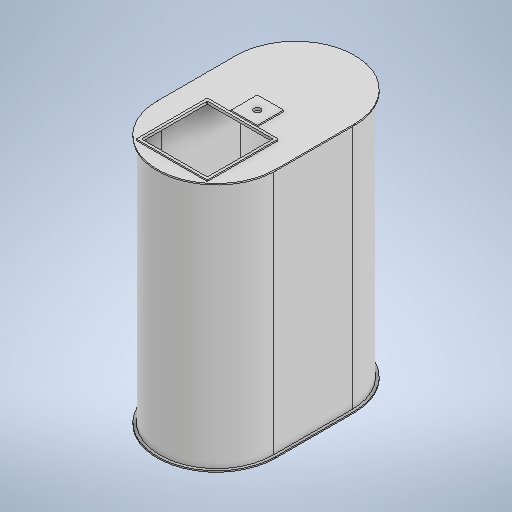
# Autodesk Inventor part: RDS-1001 Tank 2m3 Parfino
Saved by Autodesk Inventor 2026 (Build 300175000, 175)
## iProperties
Created: 2026-10-12
Part Number: RDS-1001 Tank 2m3 Parfino
Material: Generic
Description: Tank 2 m3 Parfino, obround 1500x860 H1900, wall 10
Document SubType Name: Modeling
Designer: admin
Stock Number: Емкость 2 м3 Парфино (ПЭ), овал 1500х860, H1900
Mass: 95905.8 g
Surface Area: 191956 cm^2
Volume: 95905.8 cm^3
Density: 1 g/cm^3
Appearance: Default
Author: admin
Autodesk Inventor part; units mm, degrees
ref_plane "YZ Plane" through (0, 0, 0) normal (1, 0, 0) x (0, 1, 0)
ref_plane "XZ Plane" through (0, 0, 0) normal (0, 1, 0) x (-1, 0, 0)
ref_plane "XY Plane" through (0, 0, 0) normal (0, 0, 1) x (1, 0, 0)
sketch "Sketch1" plane through (0, 0, 0) normal (0, 1, 0) x (-1, 0, 0)
  line L0 (-430, -320) -> (-430, 280)
  line L1 (430, 280) -> (430, -320)
  arc A0 (430, 280) -> (-430, 280) centre (0, 280) ccw
  arc A1 (-430, -320) -> (430, -320) centre (0, -320) ccw
  dimension "d0" = 430
  dimension "d1" = 600
  constraints: 4 end point, 4 point on circle, 4 tangent, 2 centre point, 1 equal radius
  measures "d0" radius of A0
  measures "d1" distance of L0.start L0.end
extrude "Extrusion1" add sketch "Sketch1" along normal blind 1900
shell "Shell1" thickness 10 removed faces 0
sketch "Sketch3" plane through (0, 1900, 0) normal (0, 1, 0) x (1, 0, 0)
  circle A0 centre (0, 370) radius 50
  circle A1 centre (0, -300) radius 250
  line L0 (-430, 320) -> (-430, -280) projected
  point P0 (-430, 20)
  point P1 (-430, 20)
  dimension "d10" = 100
  dimension "d11" = 500
  dimension "d14" = 320
  dimension "d15" = 430
  dimension "d16" = 350
  dimension "d17" = 430
  constraints: 2 centre point, 2 midpoint
  measures "d10" diameter of A0
  measures "d11" diameter of A1
  measures "d14" vertical distance of point (-430, 20) A1.centre
  measures "d15" distance from line of A1.centre L0
  measures "d16" vertical distance of point (-430, 20) A0.centre
  measures "d17" distance from line of A0.centre L0
extrude "Extrusion3" cut sketch "Sketch3" along normal mid plane 40
sketch "Эскиз4" plane through (0, 0, 0) normal (0, -1, 0) x (1, 0, 0)
  arc A0 (430, 280) -> (-430, 280) centre (0, 280) ccw projected
  arc A1 (450, 280) -> (-450, 280) centre (0, 280) ccw
  arc A2 (-430, -320) -> (430, -320) centre (0, -320) ccw projected
  arc A3 (-450, -320) -> (450, -320) centre (0, -320) ccw
  line L0 (-450, 280) -> (-450, -320)
  line L1 (450, -320) -> (450, 280)
  point P0 (0, 0)
  dimension "d18" = 900
  dimension "d19" = 900
  dimension "d20" = 600
  dimension "d21" = 450
  dimension "d22" = 450
  constraints: 4 end point, 4 point on circle, 2 centre point, 2 coincident, 1 parallel
  measures "d18" diameter of A1
  measures "d19" diameter of A3
  measures "d20" distance of L1.start L1.end
  measures "d21" distance from line of point (0, 0) L1
  measures "d22" distance from line of point (0, 0) L0
extrude "Выдавливание4" add sketch "Эскиз4" against normal blind 10
sketch "Эскиз5" plane through (0, 1900, 0) normal (0, 1, 0) x (1, 0, 0)
  arc A0 (450, 320) -> (-450, 320) centre (0, 320) ccw projected
  arc A1 (450, 320) -> (-450, 320) centre (0, 320) ccw
  arc A2 (-450, -280) -> (450, -280) centre (0, -280) ccw projected
  arc A3 (-450, -280) -> (450, -280) centre (0, -280) ccw
  line L0 (450, -280) -> (450, 320) projected
  line L1 (450, 320) -> (450, -280)
  line L2 (-450, -280) -> (-450, 320)
  point P0 (0, 0)
  dimension "d26" = 900
  dimension "d27" = 450
  constraints: 4 end point, 4 point on circle, 2 centre point, 2 coincident, 1 parallel, 1 point on line
  measures "d26" diameter of A3
  measures "d27" distance from line of point (0, 0) L2
extrude "Выдавливание5" add sketch "Эскиз5" against normal blind 10
sketch "Эскиз6" plane through (0, 1900, 0) normal (0, 1, 0) x (1, 0, 0)
  line L0 (245, -600) -> (-245, -600)
  line L1 (-250, -595) -> (-250, -105)
  line L2 (-245, -100) -> (245, -100)
  line L3 (250, -105) -> (250, -595)
  line L4 (250, -600) -> (-250, -100) construction
  line L5 (-250, -600) -> (250, -100) construction
  circle A0 centre (0, 30) radius 25
  line L6 (-450, 320) -> (-450, -280) projected
  arc A1 (-250, -595) -> (-245, -600) centre (-245, -595) ccw
  arc A2 (-245, -100) -> (-250, -105) centre (-245, -105) ccw
  arc A3 (250, -105) -> (245, -100) centre (245, -105) ccw
  arc A4 (245, -600) -> (250, -595) centre (245, -595) ccw
  point P0 (0, 0)
  point P1 (0, -350)
  point P2 (-250, -350)
  dimension "d30" = 500
  dimension "d31" = 500
  dimension "d32" = 350
  dimension "d33" = 250
  dimension "d34" = 50
  dimension "d35" = 30
  dimension "d36" = 450
  dimension "d39" = 5
  constraints: 12 end point, 8 point on circle, 8 point on line, 8 tangent, 5 centre point, 3 equal radius, 3 midpoint, 2 parallel, 1 horizontal, 1 perpendicular
  measures "d30" distance of L4.end L5.end
  measures "d31" distance of L5.start L4.end
  measures "d32" vertical distance of point (0, 0) point (-250, -350)
  measures "d33" distance from line of point (0, 0) L1
  measures "d34" diameter of A0
  measures "d35" distance of point (0, 0) A0.centre
  measures "d36" distance from line of A0.centre L6
  measures "d39" radius of A1
extrude "Выдавливание6" cut sketch "Эскиз6" against normal blind 10
sketch "Эскиз7" plane through (0, 1900, 0) normal (0, 1, 0) x (1, 0, 0)
  line L0 (100, -70) -> (-100, -70)
  line L1 (-100, -70) -> (-100, 130)
  line L2 (-100, 130) -> (100, 130)
  line L3 (100, 130) -> (100, -70)
  circle A0 centre (0, 30) radius 25 projected
  line L4 (100, -70) -> (-100, 130) construction
  line L5 (-100, -70) -> (100, 130) construction
  line L6 (245, -100) -> (-245, -100) projected
  arc A1 (-245, -100) -> (-250, -105) centre (-245, -105) ccw projected
  line L7 (-250, -105) -> (-250, -595) projected
  line L8 (250, -595) -> (250, -105) projected
  line L9 (-245, -600) -> (245, -600) projected
  arc A2 (245, -600) -> (250, -595) centre (245, -595) ccw projected
  arc A3 (250, -105) -> (245, -100) centre (245, -105) ccw projected
  line L10 (245, -600) -> (-245, -600) projected
  line L11 (245, -600) -> (-245, -600) projected
  line L12 (-245, -600) -> (245, -600) projected
  line L13 (-245, -100) -> (245, -100) projected
  line L14 (245, -100) -> (-245, -100) projected
  line L15 (250, -105) -> (250, -595) projected
  line L16 (250, -105) -> (250, -595) projected
  line L17 (250, -595) -> (250, -105) projected
  arc A4 (250, -105) -> (245, -100) centre (245, -105) ccw projected
  arc A5 (250, -105) -> (245, -100) centre (245, -105) ccw projected
  arc A6 (250, -105) -> (245, -100) centre (245, -105) ccw projected
  arc A7 (245, -600) -> (250, -595) centre (245, -595) ccw projected
  arc A8 (245, -600) -> (250, -595) centre (245, -595) ccw projected
  arc A9 (245, -600) -> (250, -595) centre (245, -595) ccw projected
  arc A10 (-245, -100) -> (-250, -105) centre (-245, -105) ccw projected
  line L18 (-250, -595) -> (-250, -105) projected
  arc A11 (-250, -595) -> (-245, -600) centre (-245, -595) ccw projected
  arc A12 (-245, -100) -> (-250, -105) centre (-245, -105) ccw projected
  arc A13 (-245, -100) -> (-250, -105) centre (-245, -105) ccw projected
  line L19 (-245, -100) -> (245, -100) projected
  line L20 (-250, -595) -> (-250, -105) projected
  line L21 (-250, -105) -> (-250, -595) projected
  arc A14 (-250, -595) -> (-245, -600) centre (-245, -595) ccw projected
  arc A15 (-250, -595) -> (-245, -600) centre (-245, -595) ccw projected
  arc A16 (-250, -595) -> (-245, -600) centre (-245, -595) ccw projected
  line L22 (265, -80) -> (-265, -80)
  line L23 (-270, -85) -> (-270, -615)
  line L24 (-265, -620) -> (265, -620)
  line L25 (270, -615) -> (270, -85)
  line L26 (270, -80) -> (-270, -620) construction
  line L27 (-270, -80) -> (270, -620) construction
  arc A17 (-270, -615) -> (-265, -620) centre (-265, -615) ccw
  arc A18 (-265, -80) -> (-270, -85) centre (-265, -85) ccw
  arc A19 (270, -85) -> (265, -80) centre (265, -85) ccw
  arc A20 (265, -620) -> (270, -615) centre (265, -615) ccw
  point P0 (0, 0)
  point P1 (0, -350)
  point P2 (-270, -350)
  dimension "d40" = 200
  dimension "d41" = 200
  dimension "d42" = 540
  dimension "d43" = 540
  dimension "d44" = 5
  dimension "d45" = 350
  dimension "d46" = 270
  constraints: 24 end point, 8 point on circle, 8 point on line, 8 tangent, 5 midpoint, 4 centre point, 4 parallel, 3 equal radius, 2 horizontal, 2 perpendicular, 2 other
  measures "d40" distance of L1.end L2.end
  measures "d41" distance of L0.end L1.end
  measures "d42" distance of L27.end L26.end
  measures "d43" distance of L26.end L27.start
  measures "d44" radius of A17
  measures "d45" vertical distance of point (0, 0) point (-270, -350)
  measures "d46" distance from line of point (0, 0) L23
extrude "Выдавливание7" add sketch "Эскиз7" along normal blind 10
equation "\"d0\" = 0.5 * Tank01_Width"
equation "\"d1\" = Tank01_Length - Tank01_Width"
equation "\"d2\" = Tank01_Height"
equation "\"d4\" = Tank01_Wall_Thickness"
equation "\"d10\" = Tank01_Mixer_Hole_Diam"
equation "\"d12\" = 4 * Tank01_Wall_Thickness"
equation "\"Tank01_Length\" = 1460"
equation "\"Tank01_Width\" = 860"
equation "\"Tank01_Height\" = 1900"
equation "\"Tank01_Wall_Thickness\" = 10"
equation "\"Tank01_Mixer_Hole_Diam\" = 100"
body "Solid1"
